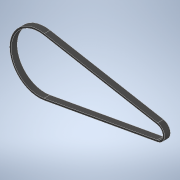
# Autodesk Inventor part: TiminigBelt_C
Saved by Autodesk Inventor 2021 (Build 250183000, 183)
## iProperties
Created: 2025-11-24
Part Number: TiminigBelt_C
Material: Rubber, Silicone
Document SubType Name: Modeling
Designer: Admin
Density: 1.25 g/cm^3
Appearance: Rubber - Black
Author: Admin
Autodesk Inventor part; units mm, degrees
ref_plane "YZ Plane" through (0, 0, 0) normal (1, 0, 0) x (0, 1, 0)
ref_plane "XZ Plane" through (0, 0, 0) normal (0, 1, 0) x (-1, 0, 0)
ref_plane "XY Plane" through (0, 0, 0) normal (0, 0, 1) x (1, 0, 0)
sketch "Sketch1" plane through (0, 0, 0) normal (0, 0, 1) x (1, 0, 0)
  arc A0 (8.4771, 46.5596) -> (8.4771, -46.5596) centre (0, 0) ccw
  arc A1 (202.0599, -11.314) -> (202.0599, 11.314) centre (200, 0) ccw
  line L0 (8.4771, 46.5596) -> (202.0599, 11.314)
  line L1 (8.4771, -46.5596) -> (202.0599, -11.314)
  line L2 (-103.29, 0) -> (267.465, 0) projected
  line L3 (202.5973, 14.2655) -> (9.0145, 49.5111)
  arc A2 (9.0145, 49.5111) -> (9.0145, -49.5111) centre (0, 0) ccw
  line L4 (9.0145, -49.5111) -> (202.5973, -14.2655)
  arc A3 (202.5973, -14.2655) -> (202.5973, 14.2655) centre (200, 0) ccw
  dimension "d0" = 200
  dimension "d1" = 94.65
  dimension "d2" = 23
  dimension "d3" = 0
  dimension "d20" = 3
  constraints: 8 end point, 8 point on circle, 4 centre point, 4 tangent, 1 coincident, 3 other
  measures "d0" distance of A1.centre point (0, 0)
  measures "d1" diameter of A0
  measures "d2" diameter of A1
  measures "d3" vertical distance of point (0, 0) A1.centre
  measures "d20" distance between parallel lines of L0 L3
extrude "Extrusion2" add sketch "Sketch1" along normal mid plane 10 contours A0 L2 A2 L3 A3 A1 L0 | A0 L1 A1 L2 A3 L4 A2
body "Solid2"
